macropad_enclosure_before_pcb_revision (Autodesk Fusion 360 design; units mm, degrees)
part number: 2026-10-12-15-45-26-429
Autodesk Fusion 360 part; units mm, degrees
(part 1 of 3)
sketch "Upper shell side profile" plane through (0, 0, 0) normal (1, 0, 0) x (0, 0, -1)
  line L0 (-2, 0) -> (-2, 115)
  line L1 (-2, 115) -> (-39.0612, 115)
  line L2 (-39.0612, 115) -> (-29, 0)
  line L3 (-29, 0) -> (-2, 0)
  dimension "d39" = 2
  dimension "d40" = 115
  dimension "d41" = 37.0612
  dimension "d42" = 27
  constraint vertical L0
  constraint horizontal L1
  constraint horizontal L3
  constraint horizontal origin L0.start
  measures "d39" horizontal distance of origin L0.start
  measures "d40" distance of L0.start L0.end
  measures "d41" distance of L0.end L1.end
  measures "d42" distance of L0.start L2.end
extrude "Upper shell wedge" add sketch "Upper shell side profile" along normal blind 80 makes body 1
shell "Open-bottom exterior shell" thickness 2.4 removed faces 1 at (53.3333, 38.3333, 2) on bodies 1
ref_plane "WorkPlane1" through (12.125, 0, 0) normal (0, -0.087156, 0.996195) x (1, 0, 0)
ref_plane "WorkPlane2" through (12.125, -2.5179, 28.7797) normal (0, -0.087156, 0.996195) x (1, 0, 0)
ref_plane "WorkPlane3" through (12.125, -2.2739, 25.9904) normal (0, -0.087156, 0.996195) x (1, 0, 0)
sketch "Middle carrier outline" plane through (0, -2.2739, 25.9904) normal (0, -0.087156, 0.996195) x (1, 0, 0)
  line L0 (2.8, 5.0932) -> (77.2, 5.0932)
  line L1 (77.2, 5.0932) -> (77.2, 114.7799)
  line L2 (77.2, 114.7799) -> (2.8, 114.7799)
  line L3 (2.8, 114.7799) -> (2.8, 5.0932)
  dimension "d52" = 2.8
  dimension "d53" = 5.0932
  dimension "d54" = 74.4
  dimension "d55" = 109.6867
  constraint horizontal L0
  constraint vertical L1
  constraint horizontal L2
  constraint vertical L3
  measures "d52" horizontal distance of origin L0.start
  measures "d53" vertical distance of origin L0.start
  measures "d54" distance of L0.start L0.end
  measures "d55" distance of L0.end L1.end
extrude "Middle carrier plate" add sketch "Middle carrier outline" against normal blind 1.5 separate body makes body 2
sketch "Carrier rear access opening" plane through (0, -2.2739, 25.9904) normal (0, -0.087156, 0.996195) x (1, 0, 0)
  line L0 (9.8, 63.2472) -> (70.2, 63.2472)
  line L1 (70.2, 63.2472) -> (70.2, 107.7799)
  line L2 (70.2, 107.7799) -> (9.8, 107.7799)
  line L3 (9.8, 107.7799) -> (9.8, 63.2472)
  dimension "d58" = 9.8
  dimension "d59" = 63.2472
  dimension "d60" = 60.4
  dimension "d61" = 44.5327
  constraint horizontal L0
  constraint vertical L1
  constraint horizontal L2
  constraint vertical L3
  measures "d58" horizontal distance of origin L0.start
  measures "d59" vertical distance of origin L0.start
  measures "d60" distance of L0.start L0.end
  measures "d61" distance of L0.end L1.end
extrude "Open carrier electronics bay" cut sketch "Carrier rear access opening" against normal blind 2.5 bodies 2
sketch "SW1 Seat profile" plane through (0, -2.2739, 25.9904) normal (0, -0.087156, 0.996195) x (1, 0, 0)
  line L0 (8.45, 19.4472) -> (22.55, 19.4472)
  line L1 (22.55, 19.4472) -> (22.55, 33.5472)
  line L2 (22.55, 33.5472) -> (8.45, 33.5472)
  line L3 (8.45, 33.5472) -> (8.45, 19.4472)
  dimension "d64" = 8.45
  dimension "d65" = 19.4472
  dimension "d66" = 14.1
  dimension "d67" = 14.1
  constraint horizontal L0
  constraint vertical L1
  constraint horizontal L2
  constraint vertical L3
  measures "d64" horizontal distance of origin L0.start
  measures "d65" vertical distance of origin L0.start
  measures "d66" distance of L0.start L0.end
  measures "d67" distance of L0.end L1.end
extrude "SW1 Seat opening" cut sketch "SW1 Seat profile" against normal blind 2.5 bodies 2
sketch "SW1 Trim profile" plane through (0, -2.5179, 28.7797) normal (0, -0.087156, 0.996195) x (1, 0, 0)
  line L0 (7.4, 18.3972) -> (23.6, 18.3972)
  line L1 (23.6, 18.3972) -> (23.6, 34.5972)
  line L2 (23.6, 34.5972) -> (7.4, 34.5972)
  line L3 (7.4, 34.5972) -> (7.4, 18.3972)
  dimension "d70" = 7.4
  dimension "d71" = 18.3972
  dimension "d72" = 16.2
  dimension "d73" = 16.2
  constraint horizontal L0
  constraint vertical L1
  constraint horizontal L2
  constraint vertical L3
  measures "d70" horizontal distance of origin L0.start
  measures "d71" vertical distance of origin L0.start
  measures "d72" distance of L0.start L0.end
  measures "d73" distance of L0.end L1.end
extrude "SW1 Trim opening" cut sketch "SW1 Trim profile" against normal blind 3.4 bodies 1
sketch "SW2 Seat profile" plane through (0, -2.2739, 25.9904) normal (0, -0.087156, 0.996195) x (1, 0, 0)
  line L0 (32.95, 19.4472) -> (47.05, 19.4472)
  line L1 (47.05, 19.4472) -> (47.05, 33.5472)
  line L2 (47.05, 33.5472) -> (32.95, 33.5472)
  line L3 (32.95, 33.5472) -> (32.95, 19.4472)
  dimension "d76" = 32.95
  dimension "d77" = 19.4472
  dimension "d78" = 14.1
  dimension "d79" = 14.1
  constraint horizontal L0
  constraint vertical L1
  constraint horizontal L2
  constraint vertical L3
  measures "d76" horizontal distance of origin L0.start
  measures "d77" vertical distance of origin L0.start
  measures "d78" distance of L0.start L0.end
  measures "d79" distance of L0.end L1.end
extrude "SW2 Seat opening" cut sketch "SW2 Seat profile" against normal blind 2.5 bodies 2
sketch "SW2 Trim profile" plane through (0, -2.5179, 28.7797) normal (0, -0.087156, 0.996195) x (1, 0, 0)
  line L0 (31.9, 18.3972) -> (48.1, 18.3972)
  line L1 (48.1, 18.3972) -> (48.1, 34.5972)
  line L2 (48.1, 34.5972) -> (31.9, 34.5972)
  line L3 (31.9, 34.5972) -> (31.9, 18.3972)
  dimension "d82" = 31.9
  dimension "d83" = 18.3972
  dimension "d84" = 16.2
  dimension "d85" = 16.2
  constraint horizontal L0
  constraint vertical L1
  constraint horizontal L2
  constraint vertical L3
  measures "d82" horizontal distance of origin L0.start
  measures "d83" vertical distance of origin L0.start
  measures "d84" distance of L0.start L0.end
  measures "d85" distance of L0.end L1.end
extrude "SW2 Trim opening" cut sketch "SW2 Trim profile" against normal blind 3.4 bodies 1
sketch "SW3 Seat profile" plane through (0, -2.2739, 25.9904) normal (0, -0.087156, 0.996195) x (1, 0, 0)
  line L0 (57.45, 19.4472) -> (71.55, 19.4472)
  line L1 (71.55, 19.4472) -> (71.55, 33.5472)
  line L2 (71.55, 33.5472) -> (57.45, 33.5472)
  line L3 (57.45, 33.5472) -> (57.45, 19.4472)
  dimension "d88" = 57.45
  dimension "d89" = 19.4472
  dimension "d90" = 14.1
  dimension "d91" = 14.1
  constraint horizontal L0
  constraint vertical L1
  constraint horizontal L2
  constraint vertical L3
  measures "d88" horizontal distance of origin L0.start
  measures "d89" vertical distance of origin L0.start
  measures "d90" distance of L0.start L0.end
  measures "d91" distance of L0.end L1.end
extrude "SW3 Seat opening" cut sketch "SW3 Seat profile" against normal blind 2.5 bodies 2
sketch "SW3 Trim profile" plane through (0, -2.5179, 28.7797) normal (0, -0.087156, 0.996195) x (1, 0, 0)
  line L0 (56.4, 18.3972) -> (72.6, 18.3972)
  line L1 (72.6, 18.3972) -> (72.6, 34.5972)
  line L2 (72.6, 34.5972) -> (56.4, 34.5972)
  line L3 (56.4, 34.5972) -> (56.4, 18.3972)
  dimension "d94" = 56.4
  dimension "d95" = 18.3972
  dimension "d96" = 16.2
  dimension "d97" = 16.2
  constraint horizontal L0
  constraint vertical L1
  constraint horizontal L2
  constraint vertical L3
  measures "d94" horizontal distance of origin L0.start
  measures "d95" vertical distance of origin L0.start
  measures "d96" distance of L0.start L0.end
  measures "d97" distance of L0.end L1.end
extrude "SW3 Trim opening" cut sketch "SW3 Trim profile" against normal blind 3.4 bodies 1
sketch "SW4 Seat profile" plane through (0, -2.2739, 25.9904) normal (0, -0.087156, 0.996195) x (1, 0, 0)
  line L0 (8.45, 43.9472) -> (22.55, 43.9472)
  line L1 (22.55, 43.9472) -> (22.55, 58.0472)
  line L2 (22.55, 58.0472) -> (8.45, 58.0472)
  line L3 (8.45, 58.0472) -> (8.45, 43.9472)
  dimension "d100" = 8.45
  dimension "d101" = 43.9472
  dimension "d102" = 14.1
  dimension "d103" = 14.1
  constraint horizontal L0
  constraint vertical L1
  constraint horizontal L2
  constraint vertical L3
  measures "d100" horizontal distance of origin L0.start
  measures "d101" vertical distance of origin L0.start
  measures "d102" distance of L0.start L0.end
  measures "d103" distance of L0.end L1.end
extrude "SW4 Seat opening" cut sketch "SW4 Seat profile" against normal blind 2.5 bodies 2
sketch "SW4 Trim profile" plane through (0, -2.5179, 28.7797) normal (0, -0.087156, 0.996195) x (1, 0, 0)
  line L0 (7.4, 42.8972) -> (23.6, 42.8972)
  line L1 (23.6, 42.8972) -> (23.6, 59.0972)
  line L2 (23.6, 59.0972) -> (7.4, 59.0972)
  line L3 (7.4, 59.0972) -> (7.4, 42.8972)
  dimension "d106" = 7.4
  dimension "d107" = 42.8972
  dimension "d108" = 16.2
  dimension "d109" = 16.2
  constraint horizontal L0
  constraint vertical L1
  constraint horizontal L2
  constraint vertical L3
  measures "d106" horizontal distance of origin L0.start
  measures "d107" vertical distance of origin L0.start
  measures "d108" distance of L0.start L0.end
  measures "d109" distance of L0.end L1.end
extrude "SW4 Trim opening" cut sketch "SW4 Trim profile" against normal blind 3.4 bodies 1
sketch "SW5 Seat profile" plane through (0, -2.2739, 25.9904) normal (0, -0.087156, 0.996195) x (1, 0, 0)
  line L0 (32.95, 43.9472) -> (47.05, 43.9472)
  line L1 (47.05, 43.9472) -> (47.05, 58.0472)
  line L2 (47.05, 58.0472) -> (32.95, 58.0472)
  line L3 (32.95, 58.0472) -> (32.95, 43.9472)
  dimension "d112" = 32.95
  dimension "d113" = 43.9472
  dimension "d114" = 14.1
  dimension "d115" = 14.1
  constraint horizontal L0
  constraint vertical L1
  constraint horizontal L2
  constraint vertical L3
  measures "d112" horizontal distance of origin L0.start
  measures "d113" vertical distance of origin L0.start
  measures "d114" distance of L0.start L0.end
  measures "d115" distance of L0.end L1.end
extrude "SW5 Seat opening" cut sketch "SW5 Seat profile" against normal blind 2.5 bodies 2
sketch "SW5 Trim profile" plane through (0, -2.5179, 28.7797) normal (0, -0.087156, 0.996195) x (1, 0, 0)
  line L0 (31.9, 42.8972) -> (48.1, 42.8972)
  line L1 (48.1, 42.8972) -> (48.1, 59.0972)
  line L2 (48.1, 59.0972) -> (31.9, 59.0972)
  line L3 (31.9, 59.0972) -> (31.9, 42.8972)
  dimension "d118" = 31.9
  dimension "d119" = 42.8972
  dimension "d120" = 16.2
  dimension "d121" = 16.2
  constraint horizontal L0
  constraint vertical L1
  constraint horizontal L2
  constraint vertical L3
  measures "d118" horizontal distance of origin L0.start
  measures "d119" vertical distance of origin L0.start
  measures "d120" distance of L0.start L0.end
  measures "d121" distance of L0.end L1.end
extrude "SW5 Trim opening" cut sketch "SW5 Trim profile" against normal blind 3.4 bodies 1
sketch "SW6 Seat profile" plane through (0, -2.2739, 25.9904) normal (0, -0.087156, 0.996195) x (1, 0, 0)
  line L0 (57.45, 43.9472) -> (71.55, 43.9472)
  line L1 (71.55, 43.9472) -> (71.55, 58.0472)
  line L2 (71.55, 58.0472) -> (57.45, 58.0472)
  line L3 (57.45, 58.0472) -> (57.45, 43.9472)
  dimension "d124" = 57.45
  dimension "d125" = 43.9472
  dimension "d126" = 14.1
  dimension "d127" = 14.1
  constraint horizontal L0
  constraint vertical L1
  constraint horizontal L2
  constraint vertical L3
  measures "d124" horizontal distance of origin L0.start
  measures "d125" vertical distance of origin L0.start
  measures "d126" distance of L0.start L0.end
  measures "d127" distance of L0.end L1.end
extrude "SW6 Seat opening" cut sketch "SW6 Seat profile" against normal blind 2.5 bodies 2
sketch "SW6 Trim profile" plane through (0, -2.5179, 28.7797) normal (0, -0.087156, 0.996195) x (1, 0, 0)
  line L0 (56.4, 42.8972) -> (72.6, 42.8972)
  line L1 (72.6, 42.8972) -> (72.6, 59.0972)
  line L2 (72.6, 59.0972) -> (56.4, 59.0972)
  line L3 (56.4, 59.0972) -> (56.4, 42.8972)
  dimension "d130" = 56.4
  dimension "d131" = 42.8972
  dimension "d132" = 16.2
  dimension "d133" = 16.2
  constraint horizontal L0
  constraint vertical L1
  constraint horizontal L2
  constraint vertical L3
  measures "d130" horizontal distance of origin L0.start
  measures "d131" vertical distance of origin L0.start
  measures "d132" distance of L0.start L0.end
  measures "d133" distance of L0.end L1.end
extrude "SW6 Trim opening" cut sketch "SW6 Trim profile" against normal blind 3.4 bodies 1
sketch "LED diffuser opening profile" plane through (0, -2.5179, 28.7797) normal (0, -0.087156, 0.996195) x (1, 0, 0)
  line L0 (6.5, 92.9972) -> (73.5, 92.9972)
  line L1 (73.5, 92.9972) -> (73.5, 102.9972)
  line L2 (73.5, 102.9972) -> (6.5, 102.9972)
  line L3 (6.5, 102.9972) -> (6.5, 92.9972)
  dimension "d136" = 6.5
  dimension "d137" = 92.9972
  dimension "d138" = 67
  dimension "d139" = 10
  constraint horizontal L0
  constraint vertical L1
  constraint horizontal L2
  constraint vertical L3
  measures "d136" horizontal distance of origin L0.start
  measures "d137" vertical distance of origin L0.start
  measures "d138" distance of L0.start L0.end
  measures "d139" distance of L0.end L1.end
extrude "LED diffuser opening" cut sketch "LED diffuser opening profile" against normal blind 3.4 bodies 1
sketch "OLED window profile" plane through (0, -2.5179, 28.7797) normal (0, -0.087156, 0.996195) x (1, 0, 0)
  line L0 (6.5, 67.2472) -> (41, 67.2472)
  line L1 (41, 67.2472) -> (41, 85.7472)
  line L2 (41, 85.7472) -> (6.5, 85.7472)
  line L3 (6.5, 85.7472) -> (6.5, 67.2472)
  dimension "d142" = 6.5
  dimension "d143" = 67.2472
  dimension "d145" = 18.5
  constraint horizontal L0
  constraint vertical L1
  constraint horizontal L2
  constraint vertical L3
  measures "d142" horizontal distance of origin L0.start
  measures "d143" vertical distance of origin L0.start
  measures "d145" distance of L0.end L1.end
extrude "OLED window" cut sketch "OLED window profile" against normal blind 3.4 bodies 1
sketch "Encoder provisional bushing profile" plane through (0, -2.5179, 28.7797) normal (0, -0.087156, 0.996195) x (1, 0, 0)
  circle A0 centre (60.5, 76.4972) radius 3.5
  dimension "d148" = 60.5
  dimension "d149" = 76.4972
  dimension "d150" = 7
  measures "d148" horizontal distance of origin A0.centre
  measures "d149" vertical distance of origin A0.centre
  measures "d150" diameter of A0
extrude "Encoder provisional opening" cut sketch "Encoder provisional bushing profile" against normal blind 3.4 bodies 1
sketch "Bottom cover outline" plane through (0, 0, 0) normal (0, 0, 1) x (1, 0, 0)
  line L0 (0, 0) -> (80, 0)
  line L1 (80, 0) -> (80, 115)
  line L2 (80, 115) -> (0, 115)
  line L3 (0, 115) -> (0, 0)
  dimension "d153" = 80
  dimension "d154" = 115
  constraint horizontal L0
  constraint vertical L1
  constraint horizontal L2
  constraint vertical L3
  constraint coincident L0.start L3.end
  measures "d153" distance of L0.start L0.end
  measures "d154" distance of L0.end L1.end
extrude "Bottom service cover" add sketch "Bottom cover outline" along normal blind 2 separate body makes body 3
sketch "Diffuser flush plug profile" plane through (0, -2.5179, 28.7797) normal (0, -0.087156, 0.996195) x (1, 0, 0)
  line L0 (6.7, 93.1972) -> (73.3, 93.1972)
  line L1 (73.3, 93.1972) -> (73.3, 102.7972)
  line L2 (73.3, 102.7972) -> (6.7, 102.7972)
  line L3 (6.7, 102.7972) -> (6.7, 93.1972)
  dimension "d157" = 6.7
  dimension "d158" = 93.1972
  dimension "d159" = 66.6
  dimension "d160" = 9.6
  constraint horizontal L0
  constraint vertical L1
  constraint horizontal L2
  constraint vertical L3
  measures "d157" horizontal distance of origin L0.start
  measures "d158" vertical distance of origin L0.start
  measures "d159" distance of L0.start L0.end
  measures "d160" distance of L0.end L1.end
extrude "Diffuser flush plug" add sketch "Diffuser flush plug profile" against normal blind 2.4 separate body makes body 4
ref_plane "WorkPlane4" through (12.125, -2.3087, 26.3888) normal (0, -0.087156, 0.996195) x (1, 0, 0)
sketch "Diffuser retaining flange profile" plane through (0, -2.3087, 26.3888) normal (0, -0.087156, 0.996195) x (1, 0, 0)
  line L0 (5.2, 91.6972) -> (74.8, 91.6972)
  line L1 (74.8, 91.6972) -> (74.8, 104.2972)
  line L2 (74.8, 104.2972) -> (5.2, 104.2972)
  line L3 (5.2, 104.2972) -> (5.2, 91.6972)
  dimension "d165" = 5.2
  dimension "d166" = 91.6972
  dimension "d167" = 69.6
  dimension "d168" = 12.6
  constraint horizontal L0
  constraint vertical L1
  constraint horizontal L2
  constraint vertical L3
  measures "d165" horizontal distance of origin L0.start
  measures "d166" vertical distance of origin L0.start
  measures "d167" distance of L0.start L0.end
  measures "d168" distance of L0.end L1.end
extrude "Diffuser retaining flange" add sketch "Diffuser retaining flange profile" against normal blind 1 bodies 4
sketch "SW1 keycap envelope" plane through (0, -2.5179, 28.7797) normal (0, -0.087156, 0.996195) x (1, 0, 0)
  line L0 (6.5, 17.4972) -> (24.5, 17.4972) construction
  line L1 (24.5, 17.4972) -> (24.5, 35.4972) construction
  line L2 (24.5, 35.4972) -> (6.5, 35.4972) construction
  line L3 (6.5, 35.4972) -> (6.5, 17.4972) construction
  dimension "d172" = 6.5
  dimension "d173" = 17.4972
  dimension "d174" = 18
  dimension "d175" = 18
  constraint horizontal L0
  constraint vertical L1
  constraint horizontal L2
  constraint vertical L3
  measures "d172" horizontal distance of origin L0.start
  measures "d173" vertical distance of origin L0.start
  measures "d174" distance of L0.start L0.end
  measures "d175" distance of L0.end L1.end
sketch "SW2 keycap envelope" plane through (0, -2.5179, 28.7797) normal (0, -0.087156, 0.996195) x (1, 0, 0)
  line L0 (31, 17.4972) -> (49, 17.4972) construction
  line L1 (49, 17.4972) -> (49, 35.4972) construction
  line L2 (49, 35.4972) -> (31, 35.4972) construction
  line L3 (31, 35.4972) -> (31, 17.4972) construction
  dimension "d176" = 31
  dimension "d177" = 17.4972
  dimension "d178" = 18
  dimension "d179" = 18
  constraint horizontal L0
  constraint vertical L1
  constraint horizontal L2
  constraint vertical L3
  measures "d176" horizontal distance of origin L0.start
  measures "d177" vertical distance of origin L0.start
  measures "d178" distance of L0.start L0.end
  measures "d179" distance of L0.end L1.end
sketch "SW3 keycap envelope" plane through (0, -2.5179, 28.7797) normal (0, -0.087156, 0.996195) x (1, 0, 0)
  line L0 (55.5, 17.4972) -> (73.5, 17.4972) construction
  line L1 (73.5, 17.4972) -> (73.5, 35.4972) construction
  line L2 (73.5, 35.4972) -> (55.5, 35.4972) construction
  line L3 (55.5, 35.4972) -> (55.5, 17.4972) construction
  dimension "d180" = 55.5
  dimension "d181" = 17.4972
  dimension "d182" = 18
  dimension "d183" = 18
  constraint horizontal L0
  constraint vertical L1
  constraint horizontal L2
  constraint vertical L3
  measures "d180" horizontal distance of origin L0.start
  measures "d181" vertical distance of origin L0.start
  measures "d182" distance of L0.start L0.end
  measures "d183" distance of L0.end L1.end
sketch "SW4 keycap envelope" plane through (0, -2.5179, 28.7797) normal (0, -0.087156, 0.996195) x (1, 0, 0)
  line L0 (6.5, 41.9972) -> (24.5, 41.9972) construction
  line L1 (24.5, 41.9972) -> (24.5, 59.9972) construction
  line L2 (24.5, 59.9972) -> (6.5, 59.9972) construction
  line L3 (6.5, 59.9972) -> (6.5, 41.9972) construction
  dimension "d184" = 6.5
  dimension "d185" = 41.9972
  dimension "d186" = 18
  dimension "d187" = 18
  constraint horizontal L0
  constraint vertical L1
  constraint horizontal L2
  constraint vertical L3
  measures "d184" horizontal distance of origin L0.start
  measures "d185" vertical distance of origin L0.start
  measures "d186" distance of L0.start L0.end
  measures "d187" distance of L0.end L1.end
sketch "SW5 keycap envelope" plane through (0, -2.5179, 28.7797) normal (0, -0.087156, 0.996195) x (1, 0, 0)
  line L0 (31, 41.9972) -> (49, 41.9972) construction
  line L1 (49, 41.9972) -> (49, 59.9972) construction
  line L2 (49, 59.9972) -> (31, 59.9972) construction
  line L3 (31, 59.9972) -> (31, 41.9972) construction
  dimension "d188" = 31
  dimension "d189" = 41.9972
  dimension "d190" = 18
  dimension "d191" = 18
  constraint horizontal L0
  constraint vertical L1
  constraint horizontal L2
  constraint vertical L3
  measures "d188" horizontal distance of origin L0.start
  measures "d189" vertical distance of origin L0.start
  measures "d190" distance of L0.start L0.end
  measures "d191" distance of L0.end L1.end
sketch "SW6 keycap envelope" plane through (0, -2.5179, 28.7797) normal (0, -0.087156, 0.996195) x (1, 0, 0)
  line L0 (55.5, 41.9972) -> (73.5, 41.9972) construction
  line L1 (73.5, 41.9972) -> (73.5, 59.9972) construction
  line L2 (73.5, 59.9972) -> (55.5, 59.9972) construction
  line L3 (55.5, 59.9972) -> (55.5, 41.9972) construction
  dimension "d192" = 55.5
  dimension "d193" = 41.9972
  dimension "d194" = 18
  dimension "d195" = 18
  constraint horizontal L0
  constraint vertical L1
  constraint horizontal L2
  constraint vertical L3
  measures "d192" horizontal distance of origin L0.start
  measures "d193" vertical distance of origin L0.start
  measures "d194" distance of L0.start L0.end
  measures "d195" distance of L0.end L1.end
sketch "Encoder knob envelope - provisional diameter" plane through (0, -2.5179, 28.7797) normal (0, -0.087156, 0.996195) x (1, 0, 0)
  circle A0 centre (60.5, 76.4972) radius 10 construction
  dimension "d196" = 60.5
  dimension "d197" = 76.4972
  dimension "d198" = 20
  measures "d196" horizontal distance of origin A0.centre
  measures "d197" vertical distance of origin A0.centre
  measures "d198" diameter of A0
sketch "Diffuser flange carrier pocket profile" plane through (0, -2.2739, 25.9904) normal (0, -0.087156, 0.996195) x (1, 0, 0)
  line L0 (5, 91.4972) -> (75, 91.4972)
  line L1 (75, 91.4972) -> (75, 104.4972)
  line L2 (75, 104.4972) -> (5, 104.4972)
  line L3 (5, 104.4972) -> (5, 91.4972)
  dimension "d200" = 5
  dimension "d201" = 91.4972
  dimension "d202" = 70
  dimension "d203" = 13
  constraint horizontal L0
  constraint vertical L1
  constraint horizontal L2
  constraint vertical L3
  measures "d200" horizontal distance of origin L0.start
  measures "d201" vertical distance of origin L0.start
  measures "d202" distance of L0.start L0.end
  measures "d203" distance of L0.end L1.end
extrude "Diffuser flange carrier recess" cut sketch "Diffuser flange carrier pocket profile" against normal blind 0.8 bodies 2
ref_plane "WorkPlane5" through (12.125, -1.8729, 21.4079) normal (0, -0.087156, 0.996195) x (1, 0, 0)
ref_plane "WorkPlane6" through (12.125, -1.8381, 21.0094) normal (0, -0.087156, 0.996195) x (1, 0, 0)
ref_plane "WorkPlane7" through (0, 0, 2) normal (0, 0, 1) x (1, 0, 0)
sketch "M1 carrier shell boss profile" plane through (0, -2.5179, 28.7797) normal (0, -0.087156, 0.996195) x (1, 0, 0)
  circle A0 centre (12, 13.0275) radius 3.5
  dimension "d230" = 12
  dimension "d232" = 7
  measures "d230" horizontal distance of origin A0.centre
  measures "d232" diameter of A0
extrude "M1 carrier shell boss" add sketch "M1 carrier shell boss profile" against normal blind 7.4 bodies 1
sketch "M1 carrier insert pilot profile" plane through (0, -1.8729, 21.4079) normal (0, -0.087156, 0.996195) x (1, 0, 0)
  circle A0 centre (12, 13.0275) radius 1.6
  dimension "d235" = 12
  dimension "d237" = 3.2
  measures "d235" horizontal distance of origin A0.centre
  measures "d237" diameter of A0
extrude "M1 carrier insert pilot" cut sketch "M1 carrier insert pilot profile" along normal blind 4.5 bodies 1
sketch "M1 carrier mounting pad profile" plane through (0, -2.2739, 25.9904) normal (0, -0.087156, 0.996195) x (1, 0, 0)
  line L0 (6, 8.3275) -> (18, 8.3275)
  line L1 (18, 8.3275) -> (18, 17.7275)
  line L2 (18, 17.7275) -> (6, 17.7275)
  line L3 (6, 17.7275) -> (6, 8.3275)
  dimension "d240" = 6
  dimension "d241" = 8.3275
  dimension "d242" = 12
  dimension "d243" = 9.4
  constraint horizontal L0
  constraint vertical L1
  constraint horizontal L2
  constraint vertical L3
  measures "d240" horizontal distance of origin L0.start
  measures "d241" vertical distance of origin L0.start
  measures "d242" distance of L0.start L0.end
  measures "d243" distance of L0.end L1.end
extrude "M1 reinforced carrier pad" add sketch "M1 carrier mounting pad profile" against normal blind 7.2 bodies 2
sketch "M1 carrier boss clearance profile" plane through (0, -1.8381, 21.0094) normal (0, -0.087156, 0.996195) x (1, 0, 0)
  circle A0 centre (12, 13.0275) radius 4.2024
  dimension "d246" = 12
  dimension "d248" = 8.4049
  measures "d246" horizontal distance of origin A0.centre
  measures "d248" diameter of A0
extrude "M1 carrier boss clearance" cut sketch "M1 carrier boss clearance profile" along normal blind 7.8 bodies 2
sketch "M1 carrier screw profile" plane through (0, -2.2739, 25.9904) normal (0, -0.087156, 0.996195) x (1, 0, 0)
  circle A0 centre (12, 13.0275) radius 1.15
  dimension "d251" = 12
  dimension "d253" = 2.3
  measures "d251" horizontal distance of origin A0.centre
  measures "d253" diameter of A0
extrude "M1 carrier screw clearance" cut sketch "M1 carrier screw profile" against normal blind 10 bodies 2
sketch "M1 bottom shell boss profile" plane through (0, 0, 2) normal (0, 0, 1) x (1, 0, 0)
  circle A0 centre (20, 4.8) radius 3
  dimension "d256" = 20
  dimension "d257" = 4.8
  dimension "d258" = 6
  measures "d256" horizontal distance of origin A0.centre
  measures "d257" vertical distance of origin A0.centre
  measures "d258" diameter of A0
extrude "M1 independent bottom boss" add sketch "M1 bottom shell boss profile" along normal blind 6 bodies 1
sketch "M1 bottom insert pilot profile" plane through (0, 0, 2) normal (0, 0, 1) x (1, 0, 0)
  circle A0 centre (20, 4.8) radius 1.6
  dimension "d261" = 20
  dimension "d262" = 4.8
  dimension "d263" = 3.2
  measures "d261" horizontal distance of origin A0.centre
  measures "d262" vertical distance of origin A0.centre
  measures "d263" diameter of A0
extrude "M1 bottom insert pilot" cut sketch "M1 bottom insert pilot profile" along normal blind 4.5 bodies 1
sketch "M1 bottom cover screw profile" plane through (0, 0, 2) normal (0, 0, 1) x (1, 0, 0)
  circle A0 centre (20, 4.8) radius 1.15
  dimension "d266" = 20
  dimension "d267" = 4.8
  dimension "d268" = 2.3
  measures "d266" horizontal distance of origin A0.centre
  measures "d267" vertical distance of origin A0.centre
  measures "d268" diameter of A0
extrude "M1 bottom cover screw clearance" cut sketch "M1 bottom cover screw profile" against normal blind 2.5 bodies 3
sketch "M2 carrier shell boss profile" plane through (0, -2.5179, 28.7797) normal (0, -0.087156, 0.996195) x (1, 0, 0)
  circle A0 centre (68, 13.0275) radius 3.5
  dimension "d271" = 68
  dimension "d273" = 7
  measures "d271" horizontal distance of origin A0.centre
  measures "d273" diameter of A0
extrude "M2 carrier shell boss" add sketch "M2 carrier shell boss profile" against normal blind 7.4 bodies 1
sketch "M2 carrier insert pilot profile" plane through (0, -1.8729, 21.4079) normal (0, -0.087156, 0.996195) x (1, 0, 0)
  circle A0 centre (68, 13.0275) radius 1.6
  dimension "d276" = 68
  dimension "d278" = 3.2
  measures "d276" horizontal distance of origin A0.centre
  measures "d278" diameter of A0
extrude "M2 carrier insert pilot" cut sketch "M2 carrier insert pilot profile" along normal blind 4.5 bodies 1
sketch "M2 carrier mounting pad profile" plane through (0, -2.2739, 25.9904) normal (0, -0.087156, 0.996195) x (1, 0, 0)
  line L0 (62, 8.3275) -> (74, 8.3275)
  line L1 (74, 8.3275) -> (74, 17.7275)
  line L2 (74, 17.7275) -> (62, 17.7275)
  line L3 (62, 17.7275) -> (62, 8.3275)
  dimension "d281" = 62
  dimension "d282" = 8.3275
  dimension "d283" = 12
  dimension "d284" = 9.4
  constraint horizontal L0
  constraint vertical L1
  constraint horizontal L2
  constraint vertical L3
  measures "d281" horizontal distance of origin L0.start
  measures "d282" vertical distance of origin L0.start
  measures "d283" distance of L0.start L0.end
  measures "d284" distance of L0.end L1.end
extrude "M2 reinforced carrier pad" add sketch "M2 carrier mounting pad profile" against normal blind 7.2 bodies 2
sketch "M2 carrier boss clearance profile" plane through (0, -1.8381, 21.0094) normal (0, -0.087156, 0.996195) x (1, 0, 0)
  circle A0 centre (68, 13.0275) radius 4.2024
  dimension "d287" = 68
  dimension "d289" = 8.4049
  measures "d287" horizontal distance of origin A0.centre
  measures "d289" diameter of A0
extrude "M2 carrier boss clearance" cut sketch "M2 carrier boss clearance profile" along normal blind 7.8 bodies 2
sketch "M2 carrier screw profile" plane through (0, -2.2739, 25.9904) normal (0, -0.087156, 0.996195) x (1, 0, 0)
  circle A0 centre (68, 13.0275) radius 1.15
  dimension "d292" = 68
  dimension "d294" = 2.3
  measures "d292" horizontal distance of origin A0.centre
  measures "d294" diameter of A0
extrude "M2 carrier screw clearance" cut sketch "M2 carrier screw profile" against normal blind 10 bodies 2
sketch "M2 bottom shell boss profile" plane through (0, 0, 2) normal (0, 0, 1) x (1, 0, 0)
  circle A0 centre (60, 4.8) radius 3
  dimension "d297" = 60
  dimension "d298" = 4.8
  dimension "d299" = 6
  measures "d297" horizontal distance of origin A0.centre
  measures "d298" vertical distance of origin A0.centre
  measures "d299" diameter of A0
extrude "M2 independent bottom boss" add sketch "M2 bottom shell boss profile" along normal blind 6 bodies 1
sketch "M2 bottom insert pilot profile" plane through (0, 0, 2) normal (0, 0, 1) x (1, 0, 0)
  circle A0 centre (60, 4.8) radius 1.6
  dimension "d302" = 60
  dimension "d303" = 4.8
  dimension "d304" = 3.2
  measures "d302" horizontal distance of origin A0.centre
  measures "d303" vertical distance of origin A0.centre
  measures "d304" diameter of A0
extrude "M2 bottom insert pilot" cut sketch "M2 bottom insert pilot profile" along normal blind 4.5 bodies 1
sketch "M2 bottom cover screw profile" plane through (0, 0, 2) normal (0, 0, 1) x (1, 0, 0)
  circle A0 centre (60, 4.8) radius 1.15
  dimension "d307" = 60
  dimension "d308" = 4.8
  dimension "d309" = 2.3
  measures "d307" horizontal distance of origin A0.centre
  measures "d308" vertical distance of origin A0.centre
  measures "d309" diameter of A0
extrude "M2 bottom cover screw clearance" cut sketch "M2 bottom cover screw profile" against normal blind 2.5 bodies 3
sketch "M3 carrier shell boss profile" plane through (0, -2.5179, 28.7797) normal (0, -0.087156, 0.996195) x (1, 0, 0)
  circle A0 centre (12, 108.3268) radius 3.5
  dimension "d312" = 12
  dimension "d314" = 7
  measures "d312" horizontal distance of origin A0.centre
  measures "d314" diameter of A0
extrude "M3 carrier shell boss" add sketch "M3 carrier shell boss profile" against normal blind 7.4 bodies 1
sketch "M3 carrier insert pilot profile" plane through (0, -1.8729, 21.4079) normal (0, -0.087156, 0.996195) x (1, 0, 0)
  circle A0 centre (12, 108.3268) radius 1.6
  dimension "d317" = 12
  dimension "d319" = 3.2
  measures "d317" horizontal distance of origin A0.centre
  measures "d319" diameter of A0
extrude "M3 carrier insert pilot" cut sketch "M3 carrier insert pilot profile" along normal blind 4.5 bodies 1
sketch "M3 carrier mounting pad profile" plane through (0, -2.2739, 25.9904) normal (0, -0.087156, 0.996195) x (1, 0, 0)
  line L0 (6, 103.6268) -> (18, 103.6268)
  line L1 (18, 103.6268) -> (18, 113.0268)
  line L2 (18, 113.0268) -> (6, 113.0268)
  line L3 (6, 113.0268) -> (6, 103.6268)
  dimension "d322" = 6
  dimension "d323" = 103.6268
  dimension "d324" = 12
  dimension "d325" = 9.4
  constraint horizontal L0
  constraint vertical L1
  constraint horizontal L2
  constraint vertical L3
  measures "d322" horizontal distance of origin L0.start
  measures "d323" vertical distance of origin L0.start
  measures "d324" distance of L0.start L0.end
  measures "d325" distance of L0.end L1.end
extrude "M3 reinforced carrier pad" add sketch "M3 carrier mounting pad profile" against normal blind 7.2 bodies 2
sketch "M3 carrier boss clearance profile" plane through (0, -1.8381, 21.0094) normal (0, -0.087156, 0.996195) x (1, 0, 0)
  circle A0 centre (12, 108.3268) radius 4.2024
  dimension "d328" = 12
  dimension "d330" = 8.4049
  measures "d328" horizontal distance of origin A0.centre
  measures "d330" diameter of A0
extrude "M3 carrier boss clearance" cut sketch "M3 carrier boss clearance profile" along normal blind 7.8 bodies 2
sketch "M3 carrier screw profile" plane through (0, -2.2739, 25.9904) normal (0, -0.087156, 0.996195) x (1, 0, 0)
  circle A0 centre (12, 108.3268) radius 1.15
  dimension "d333" = 12
  dimension "d335" = 2.3
  measures "d333" horizontal distance of origin A0.centre
  measures "d335" diameter of A0
extrude "M3 carrier screw clearance" cut sketch "M3 carrier screw profile" against normal blind 10 bodies 2
sketch "M3 bottom shell boss profile" plane through (0, 0, 2) normal (0, 0, 1) x (1, 0, 0)
  circle A0 centre (20, 112) radius 3
  dimension "d338" = 20
  dimension "d339" = 112
  dimension "d340" = 6
  measures "d338" horizontal distance of origin A0.centre
  measures "d339" vertical distance of origin A0.centre
  measures "d340" diameter of A0
extrude "M3 independent bottom boss" add sketch "M3 bottom shell boss profile" along normal blind 6 bodies 1
sketch "M3 bottom insert pilot profile" plane through (0, 0, 2) normal (0, 0, 1) x (1, 0, 0)
  circle A0 centre (20, 112) radius 1.6
  dimension "d343" = 20
  dimension "d344" = 112
  dimension "d345" = 3.2
  measures "d343" horizontal distance of origin A0.centre
  measures "d344" vertical distance of origin A0.centre
  measures "d345" diameter of A0
extrude "M3 bottom insert pilot" cut sketch "M3 bottom insert pilot profile" along normal blind 4.5 bodies 1
sketch "M3 bottom cover screw profile" plane through (0, 0, 2) normal (0, 0, 1) x (1, 0, 0)
  circle A0 centre (20, 112) radius 1.15
  dimension "d348" = 20
  dimension "d349" = 112
  dimension "d350" = 2.3
  measures "d348" horizontal distance of origin A0.centre
  measures "d349" vertical distance of origin A0.centre
  measures "d350" diameter of A0
extrude "M3 bottom cover screw clearance" cut sketch "M3 bottom cover screw profile" against normal blind 2.5 bodies 3
sketch "M4 carrier shell boss profile" plane through (0, -2.5179, 28.7797) normal (0, -0.087156, 0.996195) x (1, 0, 0)
  circle A0 centre (68, 108.3268) radius 3.5
  dimension "d353" = 68
  dimension "d355" = 7
  measures "d353" horizontal distance of origin A0.centre
  measures "d355" diameter of A0
extrude "M4 carrier shell boss" add sketch "M4 carrier shell boss profile" against normal blind 7.4 bodies 1
sketch "M4 carrier insert pilot profile" plane through (0, -1.8729, 21.4079) normal (0, -0.087156, 0.996195) x (1, 0, 0)
  circle A0 centre (68, 108.3268) radius 1.6
  dimension "d358" = 68
  dimension "d360" = 3.2
  measures "d358" horizontal distance of origin A0.centre
  measures "d360" diameter of A0
extrude "M4 carrier insert pilot" cut sketch "M4 carrier insert pilot profile" along normal blind 4.5 bodies 1
sketch "M4 carrier mounting pad profile" plane through (0, -2.2739, 25.9904) normal (0, -0.087156, 0.996195) x (1, 0, 0)
  line L0 (62, 103.6268) -> (74, 103.6268)
  line L1 (74, 103.6268) -> (74, 113.0268)
  line L2 (74, 113.0268) -> (62, 113.0268)
  line L3 (62, 113.0268) -> (62, 103.6268)
  dimension "d363" = 62
  dimension "d364" = 103.6268
  dimension "d365" = 12
  dimension "d366" = 9.4
  constraint horizontal L0
  constraint vertical L1
  constraint horizontal L2
  constraint vertical L3
  measures "d363" horizontal distance of origin L0.start
  measures "d364" vertical distance of origin L0.start
  measures "d365" distance of L0.start L0.end
  measures "d366" distance of L0.end L1.end
extrude "M4 reinforced carrier pad" add sketch "M4 carrier mounting pad profile" against normal blind 7.2 bodies 2
sketch "M4 carrier boss clearance profile" plane through (0, -1.8381, 21.0094) normal (0, -0.087156, 0.996195) x (1, 0, 0)
  circle A0 centre (68, 108.3268) radius 4.2024
  dimension "d369" = 68
  dimension "d371" = 8.4049
  measures "d369" horizontal distance of origin A0.centre
  measures "d371" diameter of A0
extrude "M4 carrier boss clearance" cut sketch "M4 carrier boss clearance profile" along normal blind 7.8 bodies 2
sketch "M4 carrier screw profile" plane through (0, -2.2739, 25.9904) normal (0, -0.087156, 0.996195) x (1, 0, 0)
  circle A0 centre (68, 108.3268) radius 1.15
  dimension "d374" = 68
  dimension "d376" = 2.3
  measures "d374" horizontal distance of origin A0.centre
  measures "d376" diameter of A0
extrude "M4 carrier screw clearance" cut sketch "M4 carrier screw profile" against normal blind 10 bodies 2
sketch "M4 bottom shell boss profile" plane through (0, 0, 2) normal (0, 0, 1) x (1, 0, 0)
  circle A0 centre (60, 112) radius 3
  dimension "d379" = 60
  dimension "d380" = 112
  dimension "d381" = 6
  measures "d379" horizontal distance of origin A0.centre
  measures "d380" vertical distance of origin A0.centre
  measures "d381" diameter of A0
extrude "M4 independent bottom boss" add sketch "M4 bottom shell boss profile" along normal blind 6 bodies 1
sketch "M4 bottom insert pilot profile" plane through (0, 0, 2) normal (0, 0, 1) x (1, 0, 0)
  circle A0 centre (60, 112) radius 1.6
  dimension "d384" = 60
  dimension "d385" = 112
  dimension "d386" = 3.2
  measures "d384" horizontal distance of origin A0.centre
  measures "d385" vertical distance of origin A0.centre
  measures "d386" diameter of A0
extrude "M4 bottom insert pilot" cut sketch "M4 bottom insert pilot profile" along normal blind 4.5 bodies 1
sketch "M4 bottom cover screw profile" plane through (0, 0, 2) normal (0, 0, 1) x (1, 0, 0)
  circle A0 centre (60, 112) radius 1.15
  dimension "d389" = 60
  dimension "d390" = 112
  dimension "d391" = 2.3
  measures "d389" horizontal distance of origin A0.centre
  measures "d390" vertical distance of origin A0.centre
  measures "d391" diameter of A0
extrude "M4 bottom cover screw clearance" cut sketch "M4 bottom cover screw profile" against normal blind 2.5 bodies 3
sketch "Switch column rib 1 profile" plane through (0, -2.2739, 25.9904) normal (0, -0.087156, 0.996195) x (1, 0, 0)
  line L0 (26.75, 17.7275) -> (28.75, 17.7275)
  line L1 (28.75, 17.7275) -> (28.75, 60.9972)
  line L2 (28.75, 60.9972) -> (26.75, 60.9972)
  line L3 (26.75, 60.9972) -> (26.75, 17.7275)
  dimension "d394" = 26.75
  dimension "d395" = 17.7275
  dimension "d396" = 2
  dimension "d397" = 43.2696
  constraint horizontal L0
  constraint vertical L1
  constraint horizontal L2
  constraint vertical L3
  measures "d394" horizontal distance of origin L0.start
  measures "d395" vertical distance of origin L0.start
  measures "d396" distance of L0.start L0.end
  measures "d397" distance of L0.end L1.end
extrude "Switch column reinforcement 1" add sketch "Switch column rib 1 profile" against normal blind 4.5 bodies 2
sketch "Switch column rib 2 profile" plane through (0, -2.2739, 25.9904) normal (0, -0.087156, 0.996195) x (1, 0, 0)
  line L0 (51.25, 17.7275) -> (53.25, 17.7275)
  line L1 (53.25, 17.7275) -> (53.25, 60.9972)
  line L2 (53.25, 60.9972) -> (51.25, 60.9972)
  line L3 (51.25, 60.9972) -> (51.25, 17.7275)
  dimension "d400" = 51.25
  dimension "d401" = 17.7275
  dimension "d402" = 2
  dimension "d403" = 43.2696
  constraint horizontal L0
  constraint vertical L1
  constraint horizontal L2
  constraint vertical L3
  measures "d400" horizontal distance of origin L0.start
  measures "d401" vertical distance of origin L0.start
  measures "d402" distance of L0.start L0.end
  measures "d403" distance of L0.end L1.end
extrude "Switch column reinforcement 2" add sketch "Switch column rib 2 profile" against normal blind 4.5 bodies 2
sketch "Switch row rib profile" plane through (0, -2.2739, 25.9904) normal (0, -0.087156, 0.996195) x (1, 0, 0)
  line L0 (10, 37.7472) -> (70, 37.7472)
  line L1 (70, 37.7472) -> (70, 39.7472)
  line L2 (70, 39.7472) -> (10, 39.7472)
  line L3 (10, 39.7472) -> (10, 37.7472)
  dimension "d406" = 10
  dimension "d407" = 37.7472
  dimension "d408" = 60
  dimension "d409" = 2
  constraint horizontal L0
  constraint vertical L1
  constraint horizontal L2
  constraint vertical L3
  measures "d406" horizontal distance of origin L0.start
  measures "d407" vertical distance of origin L0.start
  measures "d408" distance of L0.start L0.end
  measures "d409" distance of L0.end L1.end
extrude "Switch row reinforcement" add sketch "Switch row rib profile" against normal blind 4.5 bodies 2
sketch "M1 carrier vertical removal relief profile" plane through (0, 0, 2) normal (0, 0, 1) x (1, 0, 0)
  circle A0 centre (20, 4.8) radius 3.2
  dimension "d414" = 20
  dimension "d415" = 4.8
  dimension "d416" = 6.4
  measures "d414" horizontal distance of origin A0.centre
  measures "d415" vertical distance of origin A0.centre
  measures "d416" diameter of A0
extrude "M1 carrier vertical removal relief" cut sketch "M1 carrier vertical removal relief profile" along normal blind 40.0612 bodies 2
sketch "M2 carrier vertical removal relief profile" plane through (0, 0, 2) normal (0, 0, 1) x (1, 0, 0)
  circle A0 centre (60, 4.8) radius 3.2
  dimension "d419" = 60
  dimension "d420" = 4.8
  dimension "d421" = 6.4
  measures "d419" horizontal distance of origin A0.centre
  measures "d420" vertical distance of origin A0.centre
  measures "d421" diameter of A0
extrude "M2 carrier vertical removal relief" cut sketch "M2 carrier vertical removal relief profile" along normal blind 40.0612 bodies 2
sketch "M3 carrier vertical removal relief profile" plane through (0, 0, 2) normal (0, 0, 1) x (1, 0, 0)
  circle A0 centre (20, 112) radius 3.2
  dimension "d424" = 20
  dimension "d425" = 112
  dimension "d426" = 6.4
  measures "d424" horizontal distance of origin A0.centre
  measures "d425" vertical distance of origin A0.centre
  measures "d426" diameter of A0
extrude "M3 carrier vertical removal relief" cut sketch "M3 carrier vertical removal relief profile" along normal blind 40.0612 bodies 2
sketch "M4 carrier vertical removal relief profile" plane through (0, 0, 2) normal (0, 0, 1) x (1, 0, 0)
  circle A0 centre (60, 112) radius 3.2
  dimension "d429" = 60
  dimension "d430" = 112
  dimension "d431" = 6.4
  measures "d429" horizontal distance of origin A0.centre
  measures "d430" vertical distance of origin A0.centre
  measures "d431" diameter of A0
extrude "M4 carrier vertical removal relief" cut sketch "M4 carrier vertical removal relief profile" along normal blind 40.0612 bodies 2
ref_plane "WorkPlane8" through (0, 0, 8.8) normal (0, 0, 1) x (1, 0, 0)
ref_plane "WorkPlane9" through (0, 0, 10.4) normal (0, 0, 1) x (1, 0, 0)
sketch "PCB underside outline - provisional position" plane through (0, 0, 8.8) normal (0, 0, 1) x (1, 0, 0)
  line L0 (5, 62.2) -> (75, 62.2) construction
  line L1 (75, 62.2) -> (75, 112.2) construction
  line L2 (75, 112.2) -> (5, 112.2) construction
  line L3 (5, 112.2) -> (5, 62.2) construction
  dimension "d452" = 5
  dimension "d453" = 62.2
  constraint horizontal L0
  constraint vertical L1
  constraint horizontal L2
  constraint vertical L3
  measures "d452" horizontal distance of origin L0.start
  measures "d453" vertical distance of origin L0.start
sketch "PCB top outline - provisional position" plane through (0, 0, 10.4) normal (0, 0, 1) x (1, 0, 0)
  line L0 (5, 62.2) -> (75, 62.2) construction
  line L1 (75, 62.2) -> (75, 112.2) construction
  line L2 (75, 112.2) -> (5, 112.2) construction
  line L3 (5, 112.2) -> (5, 62.2) construction
  dimension "d456" = 5
  dimension "d457" = 62.2
  constraint horizontal L0
  constraint vertical L1
  constraint horizontal L2
  constraint vertical L3
  measures "d456" horizontal distance of origin L0.start
  measures "d457" vertical distance of origin L0.start
sketch "PCB mounting center 1 - hole size pending" plane through (0, 0, 8.8) normal (0, 0, 1) x (1, 0, 0)
  point P0 (7, 64.2)
  dimension "d460" = 7
  dimension "d461" = 64.2
  measures "d460" horizontal distance of origin P0
  measures "d461" vertical distance of origin P0
sketch "PCB mounting center 2 - hole size pending" plane through (0, 0, 8.8) normal (0, 0, 1) x (1, 0, 0)
  point P0 (73, 64.2)
  dimension "d462" = 73
  dimension "d463" = 64.2
  measures "d462" horizontal distance of origin P0
  measures "d463" vertical distance of origin P0
sketch "PCB mounting center 3 - hole size pending" plane through (0, 0, 8.8) normal (0, 0, 1) x (1, 0, 0)
  point P0 (7, 110.2)
  dimension "d464" = 7
  dimension "d465" = 110.2
  measures "d464" horizontal distance of origin P0
  measures "d465" vertical distance of origin P0
sketch "PCB mounting center 4 - hole size pending" plane through (0, 0, 8.8) normal (0, 0, 1) x (1, 0, 0)
  point P0 (73, 110.2)
  dimension "d466" = 73
  dimension "d467" = 110.2
  measures "d466" horizontal distance of origin P0
  measures "d467" vertical distance of origin P0
sketch "Iteration 3 diffuser flange clearance profile" plane through (0, -2.2739, 25.9904) normal (0, -0.087156, 0.996195) x (1, 0, 0)
  line L0 (5, 91.4972) -> (75, 91.4972)
  line L1 (75, 91.4972) -> (75, 104.4972)
  line L2 (75, 104.4972) -> (5, 104.4972)
  line L3 (5, 104.4972) -> (5, 91.4972)
  dimension "d476" = 5
  dimension "d477" = 91.4972
  dimension "d478" = 70
  dimension "d479" = 13
  constraint horizontal L0
  constraint vertical L1
  constraint horizontal L2
  constraint vertical L3
  measures "d476" horizontal distance of origin L0.start
  measures "d477" vertical distance of origin L0.start
  measures "d478" distance of L0.start L0.end
  measures "d479" distance of L0.end L1.end
extrude "Restore diffuser clearance in moved rear pads" cut sketch "Iteration 3 diffuser flange clearance profile" against normal blind 0.8 bodies 2
ref_plane "WorkPlane10" through (17, 0, 0) normal (1, 0, 0) x (0, 1, 0)
sketch "Front cover support 1 profile" plane through (17, 0, 0) normal (1, 0, 0) x (0, 0, -1)
  line L0 (-8, 2.3) -> (-8, 7.8)
  line L1 (-8, 7.8) -> (-13.5, 2.3)
  line L2 (-13.5, 2.3) -> (-8, 2.3)
  dimension "d484" = 8
  dimension "d485" = 2.3
  dimension "d486" = 5.5
  dimension "d487" = 5.5
  constraint vertical L0
  constraint horizontal L2
  measures "d484" horizontal distance of origin L0.start
  measures "d485" vertical distance of origin L0.start
  measures "d486" distance of L0.start L0.end
  measures "d487" distance of L0.start L1.end
extrude "Front cover support 1 45 degree gusset" add sketch "Front cover support 1 profile" along normal blind 6 bodies 1
sketch "Front support 1 removal corridor profile" plane through (0, 0, 2) normal (0, 0, 1) x (1, 0, 0)
  line L0 (16.8, 0) -> (23.2, 0)
  line L1 (23.2, 0) -> (23.2, 8)
  line L2 (23.2, 8) -> (16.8, 8)
  line L3 (16.8, 8) -> (16.8, 0)
  dimension "d490" = 16.8
  dimension "d491" = 6.4
  dimension "d492" = 8
  constraint horizontal L0
  constraint vertical L1
  constraint horizontal L2
  constraint vertical L3
  constraint horizontal origin L0.start
  measures "d490" horizontal distance of origin L0.start
  measures "d491" distance of L0.start L0.end
  measures "d492" distance of L0.end L1.end
extrude "Front support 1 vertical removal corridor" cut sketch "Front support 1 removal corridor profile" along normal blind 40.0612 bodies 2
ref_plane "WorkPlane11" through (57, 0, 0) normal (1, 0, 0) x (0, 1, 0)
sketch "Front cover support 2 profile" plane through (57, 0, 0) normal (1, 0, 0) x (0, 0, -1)
  line L0 (-8, 2.3) -> (-8, 7.8)
  line L1 (-8, 7.8) -> (-13.5, 2.3)
  line L2 (-13.5, 2.3) -> (-8, 2.3)
  dimension "d497" = 8
  dimension "d498" = 2.3
  dimension "d499" = 5.5
  dimension "d500" = 5.5
  constraint vertical L0
  constraint horizontal L2
  measures "d497" horizontal distance of origin L0.start
  measures "d498" vertical distance of origin L0.start
  measures "d499" distance of L0.start L0.end
  measures "d500" distance of L0.start L1.end
extrude "Front cover support 2 45 degree gusset" add sketch "Front cover support 2 profile" along normal blind 6 bodies 1
sketch "Front support 2 removal corridor profile" plane through (0, 0, 2) normal (0, 0, 1) x (1, 0, 0)
  line L0 (56.8, 0) -> (63.2, 0)
  line L1 (63.2, 0) -> (63.2, 8)
  line L2 (63.2, 8) -> (56.8, 8)
  line L3 (56.8, 8) -> (56.8, 0)
  dimension "d503" = 56.8
  dimension "d504" = 6.4
  dimension "d505" = 8
  constraint horizontal L0
  constraint vertical L1
  constraint horizontal L2
  constraint vertical L3
  constraint horizontal origin L0.start
  measures "d503" horizontal distance of origin L0.start
  measures "d504" distance of L0.start L0.end
  measures "d505" distance of L0.end L1.end
extrude "Front support 2 vertical removal corridor" cut sketch "Front support 2 removal corridor profile" along normal blind 40.0612 bodies 2
ref_plane "WorkPlane12" through (12.125, -2.2216, 25.3927) normal (0, -0.087156, 0.996195) x (1, 0, 0)
sketch "Diffuser hollow skirt outside profile" plane through (0, -2.2216, 25.3927) normal (0, -0.087156, 0.996195) x (1, 0, 0)
  line L0 (5.2, 91.6972) -> (74.8, 91.6972)
  line L1 (74.8, 91.6972) -> (74.8, 104.2972)
  line L2 (74.8, 104.2972) -> (5.2, 104.2972)
  line L3 (5.2, 104.2972) -> (5.2, 91.6972)
  dimension "d525" = 5.2
  dimension "d526" = 91.6972
  dimension "d527" = 69.6
  dimension "d528" = 12.6
  constraint horizontal L0
  constraint vertical L1
  constraint horizontal L2
  constraint vertical L3
  measures "d525" horizontal distance of origin L0.start
  measures "d526" vertical distance of origin L0.start
  measures "d527" distance of L0.start L0.end
  measures "d528" distance of L0.end L1.end